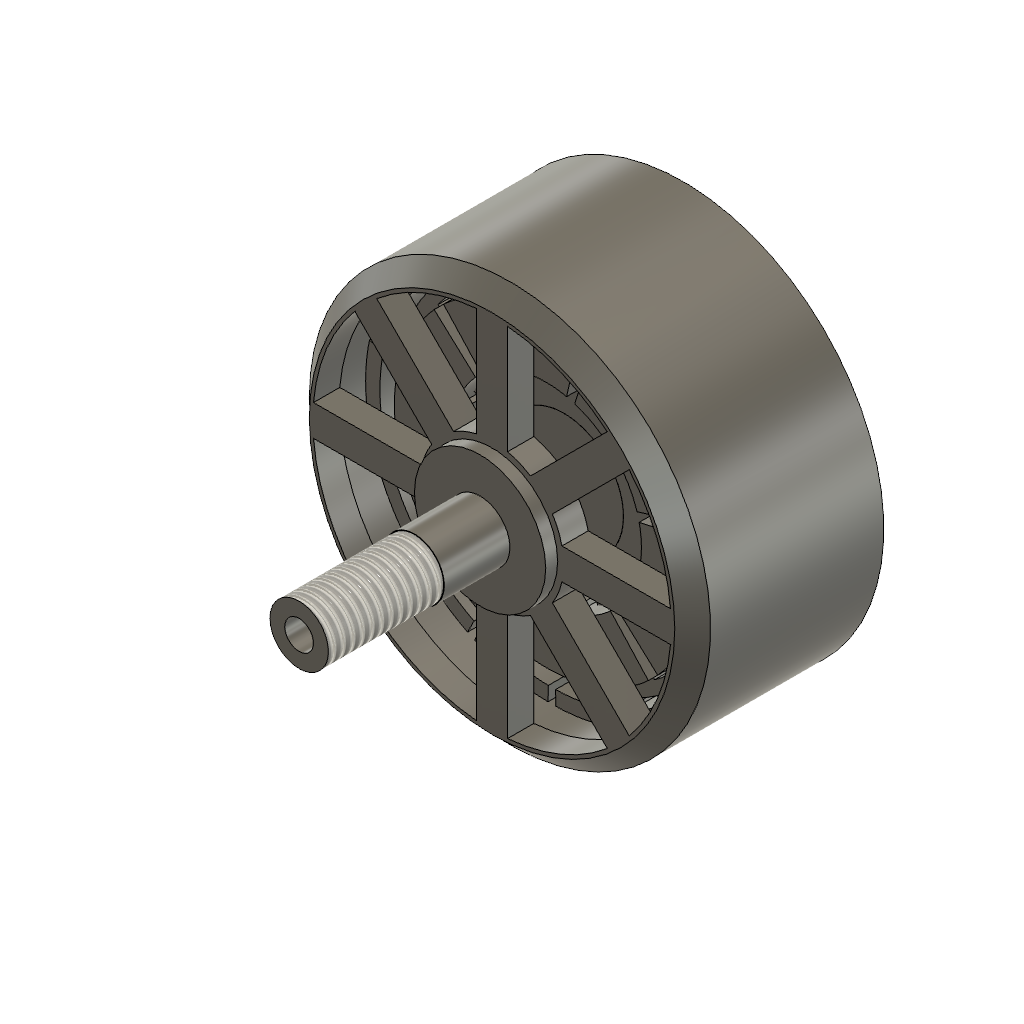
Moteur_AI2807 (Autodesk Fusion 360 design; units mm, degrees)
part number: 2026-11-11-16-03-49-779
Autodesk Fusion 360 part; units mm, degrees
sketch "Esq_embase" plane through (0, 0, 0) normal (0, 0, 1) x (1, 0, 0)
  circle A0 centre (0, 0) radius 7.22
  circle A1 centre (9.5, 0) radius 3.025
  circle A2 centre (0, 9.5) radius 3.025
  circle A3 centre (-9.5, 0) radius 3.025
  circle A4 centre (0, -9.5) radius 3.025
  dimension "d27" = 14.44
  dimension "d28" = 9.5
  dimension "d29" = 6.05
  dimension "d30" = 9.5
  dimension "d31" = 6.05
  dimension "d32" = 9.5
  dimension "d33" = 6.05
  dimension "d34" = 9.5
  dimension "d35" = 6.05
  constraint horizontal A0.centre A1.centre
  constraint vertical A0.centre A2.centre
  constraint horizontal A0.centre A3.centre
  constraint vertical A0.centre A4.centre
  measures "d27" diameter of A0
  measures "d28" horizontal distance of A0.centre A1.centre
  measures "d29" diameter of A1
  measures "d30" vertical distance of A0.centre A2.centre
  measures "d31" diameter of A2
  measures "d32" horizontal distance of A0.centre A3.centre
  measures "d33" diameter of A3
  measures "d34" vertical distance of A0.centre A4.centre
  measures "d35" diameter of A4
extrude "Embase" add sketch "Esq_embase" along normal blind 2.5 makes body 1
fillet "Raccords_embase" radius 1.2 8 edges at (-1.7206, -7.012, 1.25) (-7.012, -1.7206, 1.25) (-7.012, 1.7206, 1.25) (-1.7206, 7.012, 1.25) (1.7206, 7.012, 1.25) (7.012, 1.7206, 1.25) (7.012, -1.7206, 1.25) (1.7206, -7.012, 1.25) on bodies 1
sketch "Esq_trous_M3" plane through (0, 0, 0) normal (0, 0, 1) x (1, 0, 0)
  circle A0 centre (9.5, 0) radius 1.5
  circle A1 centre (0, 9.5) radius 1.5
  circle A2 centre (-9.5, 0) radius 1.5
  circle A3 centre (0, -9.5) radius 1.5
  dimension "d41" = 9.5
  dimension "d42" = 3
  dimension "d43" = 9.5
  dimension "d44" = 3
  dimension "d45" = 9.5
  dimension "d46" = 3
  dimension "d47" = 9.5
  dimension "d48" = 3
  constraint horizontal origin A0.centre
  constraint vertical origin A1.centre
  constraint horizontal origin A2.centre
  constraint vertical origin A3.centre
  measures "d41" horizontal distance of origin A0.centre
  measures "d42" diameter of A0
  measures "d43" vertical distance of origin A1.centre
  measures "d44" diameter of A1
  measures "d45" horizontal distance of origin A2.centre
  measures "d46" diameter of A2
  measures "d47" vertical distance of origin A3.centre
  measures "d48" diameter of A3
extrude "Trous_M3" cut sketch "Esq_trous_M3" along normal blind 2.5 bodies 1
sketch "Esq_roulement" plane through (0, 0, 0) normal (0, 0, 1) x (1, 0, 0)
  circle A0 centre (0, 0) radius 4.5
  dimension "d52" = 9
  measures "d52" diameter of A0
extrude "Logement_roulement" cut sketch "Esq_roulement" along normal blind 0.8 bodies 1
sketch "Esq_vis_arbre" plane through (0, 0, 0) normal (0, 0, 1) x (1, 0, 0)
  circle A0 centre (0, 0) radius 2
  dimension "d56" = 4
  measures "d56" diameter of A0
extrude "Vis_arbre" add sketch "Esq_vis_arbre" along normal blind 0.6 from surface at 0.2 separate body makes body 2
sketch "Esq_palier" plane through (0, 0, 0) normal (0, 0, 1) x (1, 0, 0)
  circle A0 centre (0, 0) radius 5
  dimension "d60" = 10
  measures "d60" diameter of A0
extrude "Palier" add sketch "Esq_palier" along normal blind 11 from surface at 2.5 bodies 1
sketch "Esq_culasse_stator" plane through (0, 0, 0) normal (0, 0, 1) x (1, 0, 0)
  circle A0 centre (0, 0) radius 7.5
  circle A1 centre (0, 0) radius 5
  dimension "d64" = 15
  dimension "d65" = 10
  measures "d64" diameter of A0
  measures "d65" diameter of A1
extrude "Culasse_stator" add sketch "Esq_culasse_stator" along normal blind 7 from surface at 6.5 separate body makes body 3
sketch "Esq_dents_stator" plane through (0, 0, 0) normal (0, 0, 1) x (1, 0, 0)
  circle A0 centre (0, 0) radius 7.4
  circle A1 centre (0, 0) radius 13
  circle A2 centre (0, 0) radius 14
  line L0 (7.1, 1.3) -> (13.3, 1.3)
  line L1 (7.1, -1.3) -> (13.3, -1.3)
  line L2 (12.4225, -2.6405) -> (13.9875, -2.9731)
  line L3 (12.4225, 2.6405) -> (13.9875, 2.9731)
  line L4 (5.4988, 4.6758) -> (10.8681, 7.7758)
  line L5 (6.7988, 2.4242) -> (12.1681, 5.5242)
  line L6 (12.0784, 3.9245) -> (13.6001, 4.4189)
  line L7 (9.4379, 8.498) -> (10.627, 9.5686)
  line L8 (2.4242, 6.7988) -> (5.5242, 12.1681)
  line L9 (4.6758, 5.4988) -> (7.7758, 10.8681)
  line L10 (8.498, 9.4379) -> (9.5686, 10.627)
  line L11 (3.9245, 12.0784) -> (4.4189, 13.6001)
  line L12 (-1.3, 7.1) -> (-1.3, 13.3)
  line L13 (1.3, 7.1) -> (1.3, 13.3)
  line L14 (2.6405, 12.4225) -> (2.9731, 13.9875)
  line L15 (-2.6405, 12.4225) -> (-2.9731, 13.9875)
  line L16 (-4.6758, 5.4988) -> (-7.7758, 10.8681)
  line L17 (-2.4242, 6.7988) -> (-5.5242, 12.1681)
  line L18 (-3.9245, 12.0784) -> (-4.4189, 13.6001)
  line L19 (-8.498, 9.4379) -> (-9.5686, 10.627)
  line L20 (-6.7988, 2.4242) -> (-12.1681, 5.5242)
  line L21 (-5.4988, 4.6758) -> (-10.8681, 7.7758)
  line L22 (-9.4379, 8.498) -> (-10.627, 9.5686)
  line L23 (-12.0784, 3.9245) -> (-13.6001, 4.4189)
  line L24 (-7.1, -1.3) -> (-13.3, -1.3)
  line L25 (-7.1, 1.3) -> (-13.3, 1.3)
  line L26 (-12.4225, 2.6405) -> (-13.9875, 2.9731)
  line L27 (-12.4225, -2.6405) -> (-13.9875, -2.9731)
  line L28 (-5.4988, -4.6758) -> (-10.8681, -7.7758)
  line L29 (-6.7988, -2.4242) -> (-12.1681, -5.5242)
  line L30 (-12.0784, -3.9245) -> (-13.6001, -4.4189)
  line L31 (-9.4379, -8.498) -> (-10.627, -9.5686)
  line L32 (-2.4242, -6.7988) -> (-5.5242, -12.1681)
  line L33 (-4.6758, -5.4988) -> (-7.7758, -10.8681)
  line L34 (-8.498, -9.4379) -> (-9.5686, -10.627)
  line L35 (-3.9245, -12.0784) -> (-4.4189, -13.6001)
  line L36 (1.3, -7.1) -> (1.3, -13.3)
  line L37 (-1.3, -7.1) -> (-1.3, -13.3)
  line L38 (-2.6405, -12.4225) -> (-2.9731, -13.9875)
  line L39 (2.6405, -12.4225) -> (2.9731, -13.9875)
  line L40 (4.6758, -5.4988) -> (7.7758, -10.8681)
  line L41 (2.4242, -6.7988) -> (5.5242, -12.1681)
  line L42 (3.9245, -12.0784) -> (4.4189, -13.6001)
  line L43 (8.498, -9.4379) -> (9.5686, -10.627)
  line L44 (6.7988, -2.4242) -> (12.1681, -5.5242)
  line L45 (5.4988, -4.6758) -> (10.8681, -7.7758)
  line L46 (9.4379, -8.498) -> (10.627, -9.5686)
  line L47 (12.0784, -3.9245) -> (13.6001, -4.4189)
  dimension "d69" = 14.8
  dimension "d70" = 26
  dimension "d71" = 28
  measures "d69" diameter of A0
  measures "d70" diameter of A1
  measures "d71" diameter of A2
extrude "Dents_stator" add sketch "Esq_dents_stator" along normal blind 7 from surface at 6.5 contours A0 A1 L0 L1 | A0 A1 L4 L5 | A1 A2 L2 L3 | A0 A1 L44 L45 | A1 A2 L6 L7 | A1 A2 L46 L47 | A0 A1 L8 L9 | A0 A1 L40 L41 | A1 A2 L10 L11 | A1 A2 L42 L43 | A0 A1 L12 L13 | A0 A1 L36 L37 | A1 A2 L14 L15 | A1 A2 L38 L39 | A0 A1 L16 L17 | A0 A1 L32 L33 | A1 A2 L18 L19 | A1 A2 L34 L35 | A0 A1 L20 L21 | A0 A1 L28 L29 | A1 A2 L22 L23 | A1 A2 L30 L31 | A0 A1 L24 L25 | A1 A2 L26 L27 bodies 3
sketch "Esq_bobinages" plane through (0, 0, 0) normal (0, 0, 1) x (1, 0, 0)
  circle A0 centre (0, 0) radius 8
  circle A1 centre (0, 0) radius 12.7
  line L0 (7.4198, -1.6449) -> (12.6918, -2.8137)
  line L1 (7.4198, 1.6449) -> (12.6918, 2.8137)
  line L2 (7.2482, 2.2854) -> (12.3983, 3.9092)
  line L3 (5.6033, 5.1345) -> (9.5846, 8.7827)
  line L4 (5.1345, 5.6033) -> (8.7827, 9.5846)
  line L5 (2.2854, 7.2482) -> (3.9092, 12.3983)
  line L6 (1.6449, 7.4198) -> (2.8137, 12.6918)
  line L7 (-1.6449, 7.4198) -> (-2.8137, 12.6918)
  line L8 (-2.2854, 7.2482) -> (-3.9092, 12.3983)
  line L9 (-5.1345, 5.6033) -> (-8.7827, 9.5846)
  line L10 (-5.6033, 5.1345) -> (-9.5846, 8.7827)
  line L11 (-7.2482, 2.2854) -> (-12.3983, 3.9092)
  line L12 (-7.4198, 1.6449) -> (-12.6918, 2.8137)
  line L13 (-7.4198, -1.6449) -> (-12.6918, -2.8137)
  line L14 (-7.2482, -2.2854) -> (-12.3983, -3.9092)
  line L15 (-5.6033, -5.1345) -> (-9.5846, -8.7827)
  line L16 (-5.1345, -5.6033) -> (-8.7827, -9.5846)
  line L17 (-2.2854, -7.2482) -> (-3.9092, -12.3983)
  line L18 (-1.6449, -7.4198) -> (-2.8137, -12.6918)
  line L19 (1.6449, -7.4198) -> (2.8137, -12.6918)
  line L20 (2.2854, -7.2482) -> (3.9092, -12.3983)
  line L21 (5.1345, -5.6033) -> (8.7827, -9.5846)
  line L22 (5.6033, -5.1345) -> (9.5846, -8.7827)
  line L23 (7.2482, -2.2854) -> (12.3983, -3.9092)
  dimension "d75" = 16
  dimension "d76" = 25.4
  measures "d75" diameter of A0
  measures "d76" diameter of A1
extrude "Bobinages" add sketch "Esq_bobinages" along normal blind 10 from surface at 5 separate body contours A0 A1 L0 L1 | A0 A1 L2 L3 | A0 A1 L22 L23 | A0 A1 L4 L5 | A0 A1 L20 L21 | A0 A1 L6 L7 | A0 A1 L18 L19 | A0 A1 L8 L9 | A0 A1 L16 L17 | A0 A1 L10 L11 | A0 A1 L14 L15 | A0 A1 L12 L13 makes body 4 at (-4.4015, -11.9129, 11.6667) makes body 5 at (-1.5355, 12.6068, 11.6667) makes body 6 at (11.1492, -6.0815, 11.6667) makes body 7 at (12.5176, -2.1447, 11.6667) makes body 8 at (-7.6332, 10.1501, 11.6667) makes body 9 at (-9.7682, -8.1161, 11.6667) makes body 10 at (-12.5176, -2.1447, 11.6667) makes body 11 at (8.1161, 9.7682, 8.3333) makes body 12 at (8.1161, -9.7682, 11.6667) makes body 13 at (10.8414, 6.6147, 11.6667) makes body 14 at (-11.9129, 4.4015, 11.6667) makes body 15 at (2.1447, -12.5176, 11.6667)
sketch "Esq_aimants" plane through (0, 0, 0) normal (0, 0, 1) x (1, 0, 0)
  circle A0 centre (0, 0) radius 15.61
  circle A1 centre (0, 0) radius 14.41
  line L0 (13.819, -2.851) -> (15.5818, -3.2147)
  line L1 (13.819, 2.851) -> (15.5818, 3.2147)
  line L2 (13.6875, 3.4272) -> (15.4336, 3.8644)
  line L3 (11.2135, 8.5645) -> (12.644, 9.657)
  line L4 (10.845, 9.0265) -> (12.2285, 10.178)
  line L5 (6.387, 12.5817) -> (7.2018, 14.1867)
  line L6 (5.8545, 12.8381) -> (6.6014, 14.4758)
  line L7 (0.2955, 14.1069) -> (0.3332, 15.9065)
  line L8 (-0.2955, 14.1069) -> (-0.3332, 15.9065)
  line L9 (-5.8545, 12.8381) -> (-6.6014, 14.4758)
  line L10 (-6.387, 12.5817) -> (-7.2018, 14.1867)
  line L11 (-10.845, 9.0265) -> (-12.2285, 10.178)
  line L12 (-11.2135, 8.5645) -> (-12.644, 9.657)
  line L13 (-13.6875, 3.4272) -> (-15.4336, 3.8644)
  line L14 (-13.819, 2.851) -> (-15.5818, 3.2147)
  line L15 (-13.819, -2.851) -> (-15.5818, -3.2147)
  line L16 (-13.6875, -3.4272) -> (-15.4336, -3.8644)
  line L17 (-11.2135, -8.5645) -> (-12.644, -9.657)
  line L18 (-10.845, -9.0265) -> (-12.2285, -10.178)
  line L19 (-6.387, -12.5817) -> (-7.2018, -14.1867)
  line L20 (-5.8545, -12.8381) -> (-6.6014, -14.4758)
  line L21 (-0.2955, -14.1069) -> (-0.3332, -15.9065)
  line L22 (0.2955, -14.1069) -> (0.3332, -15.9065)
  line L23 (5.8545, -12.8381) -> (6.6014, -14.4758)
  line L24 (6.387, -12.5817) -> (7.2018, -14.1867)
  line L25 (10.845, -9.0265) -> (12.2285, -10.178)
  line L26 (11.2135, -8.5645) -> (12.644, -9.657)
  line L27 (13.6875, -3.4272) -> (15.4336, -3.8644)
  dimension "d80" = 31.22
  dimension "d81" = 28.82
  measures "d80" diameter of A0
  measures "d81" diameter of A1
extrude "Aimants" add sketch "Esq_aimants" along normal blind 9 from surface at 5.5 separate body contours A0 A1 L0 L1 | A0 A1 L2 L3 | A0 A1 L26 L27 | A0 A1 L4 L5 | A0 A1 L24 L25 | A0 A1 L6 L7 | A0 A1 L22 L23 | A0 A1 L8 L9 | A0 A1 L20 L21 | A0 A1 L10 L11 | A0 A1 L18 L19 | A0 A1 L12 L13 | A0 A1 L16 L17 | A0 A1 L14 L15 makes body 16 at (-15.606, -0.3529, 11.5) makes body 17 at (1.0319, 15.5759, 11.5) makes body 18 at (14.9557, -4.472, 11.5) makes body 19 at (-5.8284, -14.4811, 8.5) makes body 20 at (15.415, -2.4599, 8.5) makes body 21 at (-5.8284, 14.4811, 11.5) makes body 22 at (-8.294, -13.2243, 11.5) makes body 23 at (-12.8211, 8.9046, 8.5) makes body 24 at (11.5343, 10.5182, 8.5) makes body 25 at (11.0471, -11.0288, 11.5) makes body 26 at (5.8284, -14.4811, 11.5) makes body 27 at (14.9557, 4.472, 8.5) makes body 28 at (-11.5343, 10.5182, 11.5) makes body 29 at (-12.8211, -8.9046, 11.5)
sketch "Esq_paroi_cloche" plane through (0, 0, 0) normal (0, 0, 1) x (1, 0, 0)
  circle A0 centre (0, 0) radius 16.81
  circle A1 centre (0, 0) radius 15.61
  dimension "d85" = 33.62
  dimension "d86" = 31.22
  measures "d85" diameter of A0
  measures "d86" diameter of A1
extrude "Paroi_cloche" add sketch "Esq_paroi_cloche" along normal blind 13.82 from surface at 3.5 separate body makes body 30
sketch "Esq_flasque_cloche" plane through (0, 0, 0) normal (0, 0, 1) x (1, 0, 0)
  circle A0 centre (0, 0) radius 16.81
  dimension "d90" = 33.62
  measures "d90" diameter of A0
extrude "Flasque_cloche" add sketch "Esq_flasque_cloche" along normal blind 2.2 from surface at 17.32 bodies 30
chamfer "Chanfrein_cloche" distance 1.5 angle 45 1 edges at (-15.6724, -6.0788, 19.52) tangent chain off on bodies 30
sketch "Esq_fenetres_cloche" plane through (0, 0, 0) normal (0, 0, 1) x (1, 0, 0)
  circle A0 centre (0, 0) radius 6
  circle A1 centre (0, 0) radius 15.01
  line L0 (4.8, -1.3) -> (15.61, -1.3)
  line L1 (4.8, 1.3) -> (15.61, 1.3)
  line L2 (4.3134, 2.4749) -> (11.9572, 10.1187)
  line L3 (2.4749, 4.3134) -> (10.1187, 11.9572)
  line L4 (1.3, 4.8) -> (1.3, 15.61)
  line L5 (-1.3, 4.8) -> (-1.3, 15.61)
  line L6 (-2.4749, 4.3134) -> (-10.1187, 11.9572)
  line L7 (-4.3134, 2.4749) -> (-11.9572, 10.1187)
  line L8 (-4.8, 1.3) -> (-15.61, 1.3)
  line L9 (-4.8, -1.3) -> (-15.61, -1.3)
  line L10 (-4.3134, -2.4749) -> (-11.9572, -10.1187)
  line L11 (-2.4749, -4.3134) -> (-10.1187, -11.9572)
  line L12 (-1.3, -4.8) -> (-1.3, -15.61)
  line L13 (1.3, -4.8) -> (1.3, -15.61)
  line L14 (2.4749, -4.3134) -> (10.1187, -11.9572)
  line L15 (4.3134, -2.4749) -> (11.9572, -10.1187)
  dimension "d95" = 12
  dimension "d96" = 30.02
  measures "d95" diameter of A0
  measures "d96" diameter of A1
extrude "Fenetres_cloche" cut sketch "Esq_fenetres_cloche" along normal blind 3.2 from surface at 16.82 contours A0 A1 L1 L2 | A0 A1 L0 L15 | A0 A1 L3 L4 | A0 A1 L13 L14 | A0 A1 L5 L6 | A0 A1 L11 L12 | A0 A1 L7 L8 | A0 A1 L9 L10 bodies 30
sketch "Esq_moyeu_cloche" plane through (0, 0, 0) normal (0, 0, 1) x (1, 0, 0)
  circle A0 centre (0, 0) radius 5.5
  dimension "d100" = 11
  measures "d100" diameter of A0
extrude "Moyeu_cloche" add sketch "Esq_moyeu_cloche" along normal blind 3.2 from surface at 17.32 bodies 30
sketch "Esq_arbre" plane through (0, 0, 0) normal (0, 0, 1) x (1, 0, 0)
  circle A0 centre (0, 0) radius 2.5
  dimension "d104" = 5
  measures "d104" diameter of A0
extrude "Arbre_filete" add sketch "Esq_arbre" along normal blind 9.66 from surface at 26.02 separate body makes body 31
thread "Filetage_M5" "ISO Metric profile 5.0 M5x0.8 M5x0.8 6g" major diameter 4.901 minor diameter 3.9895 pitch 0.8 angle 60 resizes the face on face at (2.4969, -0.1246, 32.46) on bodies 31
extrude "Arbre_lisse" add sketch "Esq_arbre" along normal blind 5.5 from surface at 20.52 bodies 31
sketch "Esq_creux_arbre" plane through (0, 0, 0) normal (0, 0, 1) x (1, 0, 0)
  circle A0 centre (0, 0) radius 1.2
  dimension "d113" = 2.4
  measures "d113" diameter of A0
extrude "Creux_arbre" cut sketch "Esq_creux_arbre" along normal blind 3 from surface at 32.68 bodies 31
equation "MOT_diam_cloche = 33.62 mm" comment "Diametre exterieur de la cloche - MESURE"
equation "MOT_hauteur_corps = 20.52 mm" comment "Dessous embase -> dessus cloche - MESURE"
equation "MOT_hauteur_totale = 35.68 mm" comment "Dessous embase -> bout de l arbre - MESURE"
equation "MOT_ext_pattes = 25.05 mm" comment "Bout a bout de deux pattes opposees - MESURE"
equation "MOT_diam_moyeu_embase = 14.44 mm" comment "Moyeu central de l embase - MESURE (interpretation)"
equation "MOT_entraxe_trous = 19 mm" comment "Diametre du cercle des 4 trous M3 - FABRICANT"
equation "MOT_diam_trou = 3 mm" comment "Trous de fixation M3 - FABRICANT"
equation "MOT_diam_arbre = 5 mm" comment "Arbre M5 - FABRICANT"
equation "MOT_diam_stator = 28 mm" comment "Diametre du stator (2807) - FABRICANT"
equation "MOT_h_stator = 7 mm" comment "Hauteur du stator (2807) - FABRICANT"
equation "MOT_ep_embase = 2.5 mm" comment "Epaisseur de l embase - ESTIME"
equation "MOT_jeu_cloche = 1 mm" comment "Jeu entre embase et bas de cloche - ESTIME"
equation "MOT_ep_paroi = 1.2 mm" comment "Epaisseur de la paroi de cloche - ESTIME"
equation "MOT_ep_aimant = 1.2 mm" comment "Epaisseur des aimants - ESTIME"
equation "MOT_h_aimant = 9 mm" comment "Hauteur des aimants - ESTIME"
equation "MOT_ep_flasque = 2.2 mm" comment "Epaisseur du flasque a rayons - ESTIME"
equation "MOT_saillie_moyeu = 1 mm" comment "Depassement du moyeu au-dessus du flasque - ESTIME"
equation "MOT_diam_moyeu_cloche = 11 mm" comment "Moyeu central de la cloche - ESTIME"
equation "MOT_chanfrein_cloche = 1.5 mm" comment "Chanfrein du haut de la cloche - ESTIME"
equation "MOT_rayon_raccord = 1.2 mm" comment "Raccords entre pattes et moyeu - ESTIME"
equation "MOT_long_lisse = 5.5 mm" comment "Partie lisse de l arbre - ESTIME"
equation "MOT_diam_roulement = 9 mm" comment "Logement du roulement sous l embase - ESTIME"
equation "MOT_z_stator = 6.5 mm" comment "Hauteur du bas du stator - ESTIME"
equation "MOT_z_cloche = MOT_ep_embase + MOT_jeu_cloche" comment "Bas de la cloche - CALCULE"
equation "MOT_z_flasque = MOT_hauteur_corps - MOT_saillie_moyeu - MOT_ep_flasque" comment "Dessous du flasque - CALCULE"
equation "MOT_long_arbre = MOT_hauteur_totale - MOT_hauteur_corps" comment "Arbre au-dessus de la cloche - CALCULE"
equation "d27 = MOT_diam_moyeu_embase"
equation "d28 = MOT_entraxe_trous / 2"
equation "d29 = MOT_ext_pattes - MOT_entraxe_trous"
equation "d30 = MOT_entraxe_trous / 2"
equation "d31 = MOT_ext_pattes - MOT_entraxe_trous"
equation "d32 = MOT_entraxe_trous / 2"
equation "d33 = MOT_ext_pattes - MOT_entraxe_trous"
equation "d34 = MOT_entraxe_trous / 2"
equation "d35 = MOT_ext_pattes - MOT_entraxe_trous"
equation "d37 = MOT_ep_embase"
equation "d40 = MOT_rayon_raccord"
equation "d41 = MOT_entraxe_trous / 2"
equation "d42 = MOT_diam_trou"
equation "d43 = MOT_entraxe_trous / 2"
equation "d44 = MOT_diam_trou"
equation "d45 = MOT_entraxe_trous / 2"
equation "d46 = MOT_diam_trou"
equation "d47 = MOT_entraxe_trous / 2"
equation "d48 = MOT_diam_trou"
equation "d50 = MOT_ep_embase"
equation "d52 = MOT_diam_roulement"
equation "d61 = MOT_ep_embase"
equation "d62 = MOT_z_stator + MOT_h_stator - MOT_ep_embase"
equation "d66 = MOT_z_stator"
equation "d67 = MOT_h_stator"
equation "d70 = MOT_diam_stator - 2 mm"
equation "d71 = MOT_diam_stator"
equation "d72 = MOT_z_stator"
equation "d73 = MOT_h_stator"
equation "d76 = MOT_diam_stator - 2.6 mm"
equation "d77 = MOT_z_stator - 1.5 mm"
equation "d78 = MOT_h_stator + 3 mm"
equation "d80 = MOT_diam_cloche - 2 * MOT_ep_paroi"
equation "d81 = MOT_diam_cloche - 2 * MOT_ep_paroi - 2 * MOT_ep_aimant"
equation "d82 = MOT_z_stator - 1 mm"
equation "d83 = MOT_h_aimant"
equation "d85 = MOT_diam_cloche"
equation "d86 = MOT_diam_cloche - 2 * MOT_ep_paroi"
equation "d87 = MOT_z_cloche"
equation "d88 = MOT_z_flasque - MOT_z_cloche"
equation "d90 = MOT_diam_cloche"
equation "d91 = MOT_z_flasque"
equation "d92 = MOT_ep_flasque"
equation "d94 = MOT_chanfrein_cloche"
equation "d95 = MOT_diam_moyeu_cloche + 1 mm"
equation "d96 = MOT_diam_cloche - 2 * MOT_ep_paroi - 1.2 mm"
equation "d97 = MOT_z_flasque - 0.5 mm"
equation "d98 = MOT_ep_flasque + 1 mm"
equation "d100 = MOT_diam_moyeu_cloche"
equation "d101 = MOT_z_flasque"
equation "d102 = MOT_ep_flasque + MOT_saillie_moyeu"
equation "d104 = MOT_diam_arbre"
equation "d105 = MOT_hauteur_corps + MOT_long_lisse"
equation "d106 = MOT_long_arbre - MOT_long_lisse"
equation "d110 = MOT_hauteur_corps"
equation "d111 = MOT_long_lisse"
equation "d114 = MOT_hauteur_totale - 3 mm"
named bodies: "Embase", "Vis_arbre", "Stator", "Bobine_01", "Bobine_02", "Bobine_03", "Bobine_04", "Bobine_05", "Bobine_06", "Bobine_07", "Bobine_08", "Bobine_09", "Bobine_10", "Bobine_11", "Bobine_12", "Aimant_01", "Aimant_02", "Aimant_03", "Aimant_04", "Aimant_05", "Aimant_06", "Aimant_07", "Aimant_08", "Aimant_09", "Aimant_10", "Aimant_11", "Aimant_12", "Aimant_13", "Aimant_14", "Cloche", "Arbre"
